Autodesk Fusion 360 part; units mm, degrees
(part 5 of 10)
sketch "Thin nut envelope sketch (6)" plane through (0, 0, 16.5) normal (0, 0, 1) x (1, 0, 0) in component "REFERENCE thin METAL channel nut front 12"
  line L0 (115.6, 222) -> (124.4, 222)
  line L1 (124.4, 222) -> (124.4, 234)
  line L2 (124.4, 234) -> (115.6, 234)
  line L3 (115.6, 234) -> (115.6, 222)
  dimension "d1899" = 115.6
  dimension "d1900" = 222
  dimension "d1901" = 8.8
  dimension "d1902" = 12
  constraint horizontal L0
  constraint vertical L1
  constraint horizontal L2
  constraint vertical L3
  measures "d1899" horizontal distance of origin L0.start
  measures "d1900" vertical distance of origin L0.start
  measures "d1901" horizontal distance of L0.start L0.end
  measures "d1902" vertical distance of L0.end L1.end
extrude "Thin nut envelope'''''" add sketch "Thin nut envelope sketch (6)" along normal blind 2.7 separate body makes body 41 in component "REFERENCE thin METAL channel nut front 12"
ref_plane "WorkPlane2" through (0, 0, 16.5) normal (0, 0, 1) x (1, 0, 0) in component "REFERENCE thin METAL channel nut front 12"
sketch "Thread envelope sketch (6)" plane through (0, 0, 16.5) normal (0, 0, 1) x (1, 0, 0) in component "REFERENCE thin METAL channel nut front 12"
  circle A0 centre (120, 228) radius 2.6
  dimension "d1907" = 120
  dimension "d1908" = 228
  dimension "d1909" = 5.2
  measures "d1907" horizontal distance of origin A0.centre
  measures "d1908" vertical distance of origin A0.centre
  measures "d1909" diameter of A0
extrude "Thread envelope'''''" cut sketch "Thread envelope sketch (6)" along normal blind 2.7 bodies 41 in component "REFERENCE thin METAL channel nut front 12"
ref_plane "WorkPlane1" through (0, 0, -5) normal (0, 0, 1) x (1, 0, 0) in component "METAL cap 20"
sketch "Visible cap sketch (7)" plane through (0, 0, -5) normal (0, 0, 1) x (1, 0, 0) in component "METAL cap 20"
  circle A0 centre (228, 12) radius 9
  dimension "d1914" = 228
  dimension "d1915" = 12
  dimension "d1916" = 18
  measures "d1914" horizontal distance of origin A0.centre
  measures "d1915" vertical distance of origin A0.centre
  measures "d1916" diameter of A0
extrude "Visible cap''''''" add sketch "Visible cap sketch (7)" along normal blind 5 separate body makes body 42 in component "METAL cap 20"
ref_plane "WorkPlane2" through (0, 0, -5) normal (0, 0, 1) x (1, 0, 0) in component "METAL cap 20"
sketch "M5 clearance sketch (7)" plane through (0, 0, -5) normal (0, 0, 1) x (1, 0, 0) in component "METAL cap 20"
  circle A0 centre (228, 12) radius 2.75
  dimension "d1921" = 228
  dimension "d1922" = 12
  dimension "d1923" = 5.5
  measures "d1921" horizontal distance of origin A0.centre
  measures "d1922" vertical distance of origin A0.centre
  measures "d1923" diameter of A0
extrude "M5 clearance''''''" cut sketch "M5 clearance sketch (7)" along normal blind 5 bodies 42 in component "METAL cap 20"
ref_plane "WorkPlane1" through (0, 0, 5) normal (0, 0, 1) x (1, 0, 0) in component "PRINT registration seat 20"
sketch "Rear bearing seat sketch (7)" plane through (0, 0, 5) normal (0, 0, 1) x (1, 0, 0) in component "PRINT registration seat 20"
  circle A0 centre (228, 12) radius 9
  dimension "d1928" = 228
  dimension "d1929" = 12
  dimension "d1930" = 18
  measures "d1928" horizontal distance of origin A0.centre
  measures "d1929" vertical distance of origin A0.centre
  measures "d1930" diameter of A0
extrude "Rear bearing seat''''''" add sketch "Rear bearing seat sketch (7)" along normal blind 2 separate body makes body 43 in component "PRINT registration seat 20"
ref_plane "WorkPlane2" through (0, 0, 5) normal (0, 0, 1) x (1, 0, 0) in component "PRINT registration seat 20"
sketch "Shoulder clearance sketch (7)" plane through (0, 0, 5) normal (0, 0, 1) x (1, 0, 0) in component "PRINT registration seat 20"
  circle A0 centre (228, 12) radius 4.2
  dimension "d1935" = 228
  dimension "d1936" = 12
  dimension "d1937" = 8.4
  measures "d1935" horizontal distance of origin A0.centre
  measures "d1936" vertical distance of origin A0.centre
  measures "d1937" diameter of A0
extrude "Shoulder clearance''''''" cut sketch "Shoulder clearance sketch (7)" along normal blind 2 bodies 43 in component "PRINT registration seat 20"
ref_plane "WorkPlane3" through (0, 0, 5) normal (0, 0, 1) x (1, 0, 0) in component "PRINT registration seat 20"
sketch "Forward registration peg sketch (9)" plane through (0, 0, 5) normal (0, 0, 1) x (1, 0, 0) in component "PRINT registration seat 20"
  circle A0 centre (223, 7) radius 1
  dimension "d1942" = 223
  dimension "d1943" = 7
  dimension "d1944" = 2
  measures "d1942" horizontal distance of origin A0.centre
  measures "d1943" vertical distance of origin A0.centre
  measures "d1944" diameter of A0
extrude "Forward registration peg''''''" add sketch "Forward registration peg sketch (9)" against normal blind 0.8 bodies 43 in component "PRINT registration seat 20"
ref_plane "WorkPlane4" through (0, 0, 5) normal (0, 0, 1) x (1, 0, 0) in component "PRINT registration seat 20"
sketch "Forward registration peg sketch (1) (7)" plane through (0, 0, 5) normal (0, 0, 1) x (1, 0, 0) in component "PRINT registration seat 20"
  circle A0 centre (223, 17) radius 1
  dimension "d1949" = 223
  dimension "d1950" = 17
  dimension "d1951" = 2
  measures "d1949" horizontal distance of origin A0.centre
  measures "d1950" vertical distance of origin A0.centre
  measures "d1951" diameter of A0
extrude "Forward registration peg (1)''''''" add sketch "Forward registration peg sketch (1) (7)" against normal blind 0.8 bodies 43 in component "PRINT registration seat 20"
ref_plane "WorkPlane5" through (0, 0, 5) normal (0, 0, 1) x (1, 0, 0) in component "PRINT registration seat 20"
sketch "Forward registration peg sketch (2) (7)" plane through (0, 0, 5) normal (0, 0, 1) x (1, 0, 0) in component "PRINT registration seat 20"
  circle A0 centre (233, 7) radius 1
  dimension "d1956" = 233
  dimension "d1957" = 7
  dimension "d1958" = 2
  measures "d1956" horizontal distance of origin A0.centre
  measures "d1957" vertical distance of origin A0.centre
  measures "d1958" diameter of A0
extrude "Forward registration peg (2)''''''" add sketch "Forward registration peg sketch (2) (7)" against normal blind 0.8 bodies 43 in component "PRINT registration seat 20"
ref_plane "WorkPlane6" through (0, 0, 5) normal (0, 0, 1) x (1, 0, 0) in component "PRINT registration seat 20"
sketch "Forward registration peg sketch (3) (7)" plane through (0, 0, 5) normal (0, 0, 1) x (1, 0, 0) in component "PRINT registration seat 20"
  circle A0 centre (233, 17) radius 1
  dimension "d1963" = 233
  dimension "d1964" = 17
  dimension "d1965" = 2
  measures "d1963" horizontal distance of origin A0.centre
  measures "d1964" vertical distance of origin A0.centre
  measures "d1965" diameter of A0
extrude "Forward registration peg (3)''''''" add sketch "Forward registration peg sketch (3) (7)" against normal blind 0.8 bodies 43 in component "PRINT registration seat 20"
sketch "8 mm shoulder sketch (7)" plane through (0, 0, 0) normal (0, 0, 1) x (1, 0, 0) in component "METAL stepped compression spacer 20"
  circle A0 centre (228, 12) radius 4
  dimension "d1968" = 228
  dimension "d1969" = 12
  dimension "d1970" = 8
  measures "d1968" horizontal distance of origin A0.centre
  measures "d1969" vertical distance of origin A0.centre
  measures "d1970" diameter of A0
extrude "8 mm shoulder''''''" add sketch "8 mm shoulder sketch (7)" along normal blind 7 separate body makes body 44 in component "METAL stepped compression spacer 20"
ref_plane "WorkPlane1" through (0, 0, 7) normal (0, 0, 1) x (1, 0, 0) in component "METAL stepped compression spacer 20"
sketch "12 mm base sketch (7)" plane through (0, 0, 7) normal (0, 0, 1) x (1, 0, 0) in component "METAL stepped compression spacer 20"
  circle A0 centre (228, 12) radius 6
  dimension "d1975" = 228
  dimension "d1976" = 12
  dimension "d1977" = 12
  measures "d1975" horizontal distance of origin A0.centre
  measures "d1976" vertical distance of origin A0.centre
  measures "d1977" diameter of A0
extrude "12 mm base''''''" add sketch "12 mm base sketch (7)" along normal blind 8 bodies 44 in component "METAL stepped compression spacer 20"
sketch "Through bore sketch (7)" plane through (0, 0, 0) normal (0, 0, 1) x (1, 0, 0) in component "METAL stepped compression spacer 20"
  circle A0 centre (228, 12) radius 2.75
  dimension "d1980" = 228
  dimension "d1981" = 12
  dimension "d1982" = 5.5
  measures "d1980" horizontal distance of origin A0.centre
  measures "d1981" vertical distance of origin A0.centre
  measures "d1982" diameter of A0
extrude "Through bore''''''" cut sketch "Through bore sketch (7)" along normal blind 15 bodies 44 in component "METAL stepped compression spacer 20"
ref_plane "WorkPlane1" through (0, 0, -8) normal (0, 0, 1) x (1, 0, 0) in component "REFERENCE front M5x25 20"
sketch "Button head envelope sketch (7)" plane through (0, 0, -8) normal (0, 0, 1) x (1, 0, 0) in component "REFERENCE front M5x25 20"
  circle A0 centre (228, 12) radius 4.75
  dimension "d1987" = 228
  dimension "d1988" = 12
  dimension "d1989" = 9.5
  measures "d1987" horizontal distance of origin A0.centre
  measures "d1988" vertical distance of origin A0.centre
  measures "d1989" diameter of A0
extrude "Button head envelope''''''" add sketch "Button head envelope sketch (7)" along normal blind 3 separate body makes body 45 in component "REFERENCE front M5x25 20"
ref_plane "WorkPlane2" through (0, 0, -5) normal (0, 0, 1) x (1, 0, 0) in component "REFERENCE front M5x25 20"
sketch "Shank envelope sketch (7)" plane through (0, 0, -5) normal (0, 0, 1) x (1, 0, 0) in component "REFERENCE front M5x25 20"
  circle A0 centre (228, 12) radius 2.5
  dimension "d1994" = 228
  dimension "d1995" = 12
  dimension "d1996" = 5
  measures "d1994" horizontal distance of origin A0.centre
  measures "d1995" vertical distance of origin A0.centre
  measures "d1996" diameter of A0
extrude "Shank envelope''''''" add sketch "Shank envelope sketch (7)" along normal blind 25 bodies 45 in component "REFERENCE front M5x25 20"
ref_plane "WorkPlane1" through (0, 0, 16.5) normal (0, 0, 1) x (1, 0, 0) in component "REFERENCE thin METAL channel nut front 20"
sketch "Thin nut envelope sketch (7)" plane through (0, 0, 16.5) normal (0, 0, 1) x (1, 0, 0) in component "REFERENCE thin METAL channel nut front 20"
  line L0 (223.6, 6) -> (232.4, 6)
  line L1 (232.4, 6) -> (232.4, 18)
  line L2 (232.4, 18) -> (223.6, 18)
  line L3 (223.6, 18) -> (223.6, 6)
  dimension "d2001" = 223.6
  dimension "d2002" = 6
  dimension "d2003" = 8.8
  dimension "d2004" = 12
  constraint horizontal L0
  constraint vertical L1
  constraint horizontal L2
  constraint vertical L3
  measures "d2001" horizontal distance of origin L0.start
  measures "d2002" vertical distance of origin L0.start
  measures "d2003" horizontal distance of L0.start L0.end
  measures "d2004" vertical distance of L0.end L1.end
extrude "Thin nut envelope''''''" add sketch "Thin nut envelope sketch (7)" along normal blind 2.7 separate body makes body 46 in component "REFERENCE thin METAL channel nut front 20"
ref_plane "WorkPlane2" through (0, 0, 16.5) normal (0, 0, 1) x (1, 0, 0) in component "REFERENCE thin METAL channel nut front 20"
sketch "Thread envelope sketch (7)" plane through (0, 0, 16.5) normal (0, 0, 1) x (1, 0, 0) in component "REFERENCE thin METAL channel nut front 20"
  circle A0 centre (228, 12) radius 2.6
  dimension "d2009" = 228
  dimension "d2010" = 12
  dimension "d2011" = 5.2
  measures "d2009" horizontal distance of origin A0.centre
  measures "d2010" vertical distance of origin A0.centre
  measures "d2011" diameter of A0
extrude "Thread envelope''''''" cut sketch "Thread envelope sketch (7)" along normal blind 2.7 bodies 46 in component "REFERENCE thin METAL channel nut front 20"
ref_plane "WorkPlane1" through (0, 0, -5) normal (0, 0, 1) x (1, 0, 0) in component "METAL cap 21"
sketch "Visible cap sketch (8)" plane through (0, 0, -5) normal (0, 0, 1) x (1, 0, 0) in component "METAL cap 21"
  circle A0 centre (228, 120) radius 9
  dimension "d2016" = 228
  dimension "d2017" = 120
  dimension "d2018" = 18
  measures "d2016" horizontal distance of origin A0.centre
  measures "d2017" vertical distance of origin A0.centre
  measures "d2018" diameter of A0
extrude "Visible cap'''''''" add sketch "Visible cap sketch (8)" along normal blind 5 separate body makes body 47 in component "METAL cap 21"
ref_plane "WorkPlane2" through (0, 0, -5) normal (0, 0, 1) x (1, 0, 0) in component "METAL cap 21"
sketch "M5 clearance sketch (8)" plane through (0, 0, -5) normal (0, 0, 1) x (1, 0, 0) in component "METAL cap 21"
  circle A0 centre (228, 120) radius 2.75
  dimension "d2023" = 228
  dimension "d2024" = 120
  dimension "d2025" = 5.5
  measures "d2023" horizontal distance of origin A0.centre
  measures "d2024" vertical distance of origin A0.centre
  measures "d2025" diameter of A0
extrude "M5 clearance'''''''" cut sketch "M5 clearance sketch (8)" along normal blind 5 bodies 47 in component "METAL cap 21"
ref_plane "WorkPlane1" through (0, 0, 5) normal (0, 0, 1) x (1, 0, 0) in component "PRINT registration seat 21"
sketch "Rear bearing seat sketch (8)" plane through (0, 0, 5) normal (0, 0, 1) x (1, 0, 0) in component "PRINT registration seat 21"
  circle A0 centre (228, 120) radius 9
  dimension "d2030" = 228
  dimension "d2031" = 120
  dimension "d2032" = 18
  measures "d2030" horizontal distance of origin A0.centre
  measures "d2031" vertical distance of origin A0.centre
  measures "d2032" diameter of A0
extrude "Rear bearing seat'''''''" add sketch "Rear bearing seat sketch (8)" along normal blind 2 separate body makes body 48 in component "PRINT registration seat 21"
ref_plane "WorkPlane2" through (0, 0, 5) normal (0, 0, 1) x (1, 0, 0) in component "PRINT registration seat 21"
sketch "Shoulder clearance sketch (8)" plane through (0, 0, 5) normal (0, 0, 1) x (1, 0, 0) in component "PRINT registration seat 21"
  circle A0 centre (228, 120) radius 4.2
  dimension "d2037" = 228
  dimension "d2038" = 120
  dimension "d2039" = 8.4
  measures "d2037" horizontal distance of origin A0.centre
  measures "d2038" vertical distance of origin A0.centre
  measures "d2039" diameter of A0
extrude "Shoulder clearance'''''''" cut sketch "Shoulder clearance sketch (8)" along normal blind 2 bodies 48 in component "PRINT registration seat 21"
ref_plane "WorkPlane3" through (0, 0, 5) normal (0, 0, 1) x (1, 0, 0) in component "PRINT registration seat 21"
sketch "Forward registration peg sketch (10)" plane through (0, 0, 5) normal (0, 0, 1) x (1, 0, 0) in component "PRINT registration seat 21"
  circle A0 centre (223, 115) radius 1
  dimension "d2044" = 223
  dimension "d2045" = 115
  dimension "d2046" = 2
  measures "d2044" horizontal distance of origin A0.centre
  measures "d2045" vertical distance of origin A0.centre
  measures "d2046" diameter of A0
extrude "Forward registration peg'''''''" add sketch "Forward registration peg sketch (10)" against normal blind 0.8 bodies 48 in component "PRINT registration seat 21"
ref_plane "WorkPlane4" through (0, 0, 5) normal (0, 0, 1) x (1, 0, 0) in component "PRINT registration seat 21"
sketch "Forward registration peg sketch (1) (8)" plane through (0, 0, 5) normal (0, 0, 1) x (1, 0, 0) in component "PRINT registration seat 21"
  circle A0 centre (223, 125) radius 1
  dimension "d2051" = 223
  dimension "d2052" = 125
  dimension "d2053" = 2
  measures "d2051" horizontal distance of origin A0.centre
  measures "d2052" vertical distance of origin A0.centre
  measures "d2053" diameter of A0
extrude "Forward registration peg (1)'''''''" add sketch "Forward registration peg sketch (1) (8)" against normal blind 0.8 bodies 48 in component "PRINT registration seat 21"
ref_plane "WorkPlane5" through (0, 0, 5) normal (0, 0, 1) x (1, 0, 0) in component "PRINT registration seat 21"
sketch "Forward registration peg sketch (2) (8)" plane through (0, 0, 5) normal (0, 0, 1) x (1, 0, 0) in component "PRINT registration seat 21"
  circle A0 centre (233, 115) radius 1
  dimension "d2058" = 233
  dimension "d2059" = 115
  dimension "d2060" = 2
  measures "d2058" horizontal distance of origin A0.centre
  measures "d2059" vertical distance of origin A0.centre
  measures "d2060" diameter of A0
extrude "Forward registration peg (2)'''''''" add sketch "Forward registration peg sketch (2) (8)" against normal blind 0.8 bodies 48 in component "PRINT registration seat 21"
ref_plane "WorkPlane6" through (0, 0, 5) normal (0, 0, 1) x (1, 0, 0) in component "PRINT registration seat 21"
sketch "Forward registration peg sketch (3) (8)" plane through (0, 0, 5) normal (0, 0, 1) x (1, 0, 0) in component "PRINT registration seat 21"
  circle A0 centre (233, 125) radius 1
  dimension "d2065" = 233
  dimension "d2066" = 125
  dimension "d2067" = 2
  measures "d2065" horizontal distance of origin A0.centre
  measures "d2066" vertical distance of origin A0.centre
  measures "d2067" diameter of A0
extrude "Forward registration peg (3)'''''''" add sketch "Forward registration peg sketch (3) (8)" against normal blind 0.8 bodies 48 in component "PRINT registration seat 21"
sketch "8 mm shoulder sketch (8)" plane through (0, 0, 0) normal (0, 0, 1) x (1, 0, 0) in component "METAL stepped compression spacer 21"
  circle A0 centre (228, 120) radius 4
  dimension "d2070" = 228
  dimension "d2071" = 120
  dimension "d2072" = 8
  measures "d2070" horizontal distance of origin A0.centre
  measures "d2071" vertical distance of origin A0.centre
  measures "d2072" diameter of A0
extrude "8 mm shoulder'''''''" add sketch "8 mm shoulder sketch (8)" along normal blind 7 separate body makes body 49 in component "METAL stepped compression spacer 21"
ref_plane "WorkPlane1" through (0, 0, 7) normal (0, 0, 1) x (1, 0, 0) in component "METAL stepped compression spacer 21"
sketch "12 mm base sketch (8)" plane through (0, 0, 7) normal (0, 0, 1) x (1, 0, 0) in component "METAL stepped compression spacer 21"
  circle A0 centre (228, 120) radius 6
  dimension "d2077" = 228
  dimension "d2078" = 120
  dimension "d2079" = 12
  measures "d2077" horizontal distance of origin A0.centre
  measures "d2078" vertical distance of origin A0.centre
  measures "d2079" diameter of A0
extrude "12 mm base'''''''" add sketch "12 mm base sketch (8)" along normal blind 8 bodies 49 in component "METAL stepped compression spacer 21"
sketch "Through bore sketch (8)" plane through (0, 0, 0) normal (0, 0, 1) x (1, 0, 0) in component "METAL stepped compression spacer 21"
  circle A0 centre (228, 120) radius 2.75
  dimension "d2082" = 228
  dimension "d2083" = 120
  dimension "d2084" = 5.5
  measures "d2082" horizontal distance of origin A0.centre
  measures "d2083" vertical distance of origin A0.centre
  measures "d2084" diameter of A0
extrude "Through bore'''''''" cut sketch "Through bore sketch (8)" along normal blind 15 bodies 49 in component "METAL stepped compression spacer 21"
ref_plane "WorkPlane1" through (0, 0, -8) normal (0, 0, 1) x (1, 0, 0) in component "REFERENCE front M5x25 21"
sketch "Button head envelope sketch (8)" plane through (0, 0, -8) normal (0, 0, 1) x (1, 0, 0) in component "REFERENCE front M5x25 21"
  circle A0 centre (228, 120) radius 4.75
  dimension "d2089" = 228
  dimension "d2090" = 120
  dimension "d2091" = 9.5
  measures "d2089" horizontal distance of origin A0.centre
  measures "d2090" vertical distance of origin A0.centre
  measures "d2091" diameter of A0
extrude "Button head envelope'''''''" add sketch "Button head envelope sketch (8)" along normal blind 3 separate body makes body 50 in component "REFERENCE front M5x25 21"
ref_plane "WorkPlane2" through (0, 0, -5) normal (0, 0, 1) x (1, 0, 0) in component "REFERENCE front M5x25 21"
sketch "Shank envelope sketch (8)" plane through (0, 0, -5) normal (0, 0, 1) x (1, 0, 0) in component "REFERENCE front M5x25 21"
  circle A0 centre (228, 120) radius 2.5
  dimension "d2096" = 228
  dimension "d2097" = 120
  dimension "d2098" = 5
  measures "d2096" horizontal distance of origin A0.centre
  measures "d2097" vertical distance of origin A0.centre
  measures "d2098" diameter of A0
extrude "Shank envelope'''''''" add sketch "Shank envelope sketch (8)" along normal blind 25 bodies 50 in component "REFERENCE front M5x25 21"
ref_plane "WorkPlane1" through (0, 0, 16.5) normal (0, 0, 1) x (1, 0, 0) in component "REFERENCE thin METAL channel nut front 21"
sketch "Thin nut envelope sketch (8)" plane through (0, 0, 16.5) normal (0, 0, 1) x (1, 0, 0) in component "REFERENCE thin METAL channel nut front 21"
  line L0 (223.6, 114) -> (232.4, 114)
  line L1 (232.4, 114) -> (232.4, 126)
  line L2 (232.4, 126) -> (223.6, 126)
  line L3 (223.6, 126) -> (223.6, 114)
  dimension "d2103" = 223.6
  dimension "d2104" = 114
  dimension "d2105" = 8.8
  dimension "d2106" = 12
  constraint horizontal L0
  constraint vertical L1
  constraint horizontal L2
  constraint vertical L3
  measures "d2103" horizontal distance of origin L0.start
  measures "d2104" vertical distance of origin L0.start
  measures "d2105" horizontal distance of L0.start L0.end
  measures "d2106" vertical distance of L0.end L1.end
extrude "Thin nut envelope'''''''" add sketch "Thin nut envelope sketch (8)" along normal blind 2.7 separate body makes body 51 in component "REFERENCE thin METAL channel nut front 21"
ref_plane "WorkPlane2" through (0, 0, 16.5) normal (0, 0, 1) x (1, 0, 0) in component "REFERENCE thin METAL channel nut front 21"
sketch "Thread envelope sketch (8)" plane through (0, 0, 16.5) normal (0, 0, 1) x (1, 0, 0) in component "REFERENCE thin METAL channel nut front 21"
  circle A0 centre (228, 120) radius 2.6
  dimension "d2111" = 228
  dimension "d2112" = 120
  dimension "d2113" = 5.2
  measures "d2111" horizontal distance of origin A0.centre
  measures "d2112" vertical distance of origin A0.centre
  measures "d2113" diameter of A0
extrude "Thread envelope'''''''" cut sketch "Thread envelope sketch (8)" along normal blind 2.7 bodies 51 in component "REFERENCE thin METAL channel nut front 21"
ref_plane "WorkPlane1" through (0, 0, -5) normal (0, 0, 1) x (1, 0, 0) in component "METAL cap 22"
sketch "Visible cap sketch (9)" plane through (0, 0, -5) normal (0, 0, 1) x (1, 0, 0) in component "METAL cap 22"
  circle A0 centre (228, 228) radius 9
  dimension "d2118" = 228
  dimension "d2119" = 228
  dimension "d2120" = 18
  measures "d2118" horizontal distance of origin A0.centre
  measures "d2119" vertical distance of origin A0.centre
  measures "d2120" diameter of A0
extrude "Visible cap''''''''" add sketch "Visible cap sketch (9)" along normal blind 5 separate body makes body 52 in component "METAL cap 22"
ref_plane "WorkPlane2" through (0, 0, -5) normal (0, 0, 1) x (1, 0, 0) in component "METAL cap 22"
sketch "M5 clearance sketch (9)" plane through (0, 0, -5) normal (0, 0, 1) x (1, 0, 0) in component "METAL cap 22"
  circle A0 centre (228, 228) radius 2.75
  dimension "d2125" = 228
  dimension "d2126" = 228
  dimension "d2127" = 5.5
  measures "d2125" horizontal distance of origin A0.centre
  measures "d2126" vertical distance of origin A0.centre
  measures "d2127" diameter of A0
extrude "M5 clearance''''''''" cut sketch "M5 clearance sketch (9)" along normal blind 5 bodies 52 in component "METAL cap 22"
ref_plane "WorkPlane1" through (0, 0, 5) normal (0, 0, 1) x (1, 0, 0) in component "PRINT registration seat 22"
sketch "Rear bearing seat sketch (9)" plane through (0, 0, 5) normal (0, 0, 1) x (1, 0, 0) in component "PRINT registration seat 22"
  circle A0 centre (228, 228) radius 9
  dimension "d2132" = 228
  dimension "d2133" = 228
  dimension "d2134" = 18
  measures "d2132" horizontal distance of origin A0.centre
  measures "d2133" vertical distance of origin A0.centre
  measures "d2134" diameter of A0
extrude "Rear bearing seat''''''''" add sketch "Rear bearing seat sketch (9)" along normal blind 2 separate body makes body 53 in component "PRINT registration seat 22"
ref_plane "WorkPlane2" through (0, 0, 5) normal (0, 0, 1) x (1, 0, 0) in component "PRINT registration seat 22"
sketch "Shoulder clearance sketch (9)" plane through (0, 0, 5) normal (0, 0, 1) x (1, 0, 0) in component "PRINT registration seat 22"
  circle A0 centre (228, 228) radius 4.2
  dimension "d2139" = 228
  dimension "d2140" = 228
  dimension "d2141" = 8.4
  measures "d2139" horizontal distance of origin A0.centre
  measures "d2140" vertical distance of origin A0.centre
  measures "d2141" diameter of A0
extrude "Shoulder clearance''''''''" cut sketch "Shoulder clearance sketch (9)" along normal blind 2 bodies 53 in component "PRINT registration seat 22"
ref_plane "WorkPlane3" through (0, 0, 5) normal (0, 0, 1) x (1, 0, 0) in component "PRINT registration seat 22"
sketch "Forward registration peg sketch (11)" plane through (0, 0, 5) normal (0, 0, 1) x (1, 0, 0) in component "PRINT registration seat 22"
  circle A0 centre (223, 223) radius 1
  dimension "d2146" = 223
  dimension "d2147" = 223
  dimension "d2148" = 2
  measures "d2146" horizontal distance of origin A0.centre
  measures "d2147" vertical distance of origin A0.centre
  measures "d2148" diameter of A0
extrude "Forward registration peg''''''''" add sketch "Forward registration peg sketch (11)" against normal blind 0.8 bodies 53 in component "PRINT registration seat 22"
ref_plane "WorkPlane4" through (0, 0, 5) normal (0, 0, 1) x (1, 0, 0) in component "PRINT registration seat 22"
sketch "Forward registration peg sketch (1) (9)" plane through (0, 0, 5) normal (0, 0, 1) x (1, 0, 0) in component "PRINT registration seat 22"
  circle A0 centre (223, 233) radius 1
  dimension "d2153" = 223
  dimension "d2154" = 233
  dimension "d2155" = 2
  measures "d2153" horizontal distance of origin A0.centre
  measures "d2154" vertical distance of origin A0.centre
  measures "d2155" diameter of A0
extrude "Forward registration peg (1)''''''''" add sketch "Forward registration peg sketch (1) (9)" against normal blind 0.8 bodies 53 in component "PRINT registration seat 22"
ref_plane "WorkPlane5" through (0, 0, 5) normal (0, 0, 1) x (1, 0, 0) in component "PRINT registration seat 22"
sketch "Forward registration peg sketch (2) (9)" plane through (0, 0, 5) normal (0, 0, 1) x (1, 0, 0) in component "PRINT registration seat 22"
  circle A0 centre (233, 223) radius 1
  dimension "d2160" = 233
  dimension "d2161" = 223
  dimension "d2162" = 2
  measures "d2160" horizontal distance of origin A0.centre
  measures "d2161" vertical distance of origin A0.centre
  measures "d2162" diameter of A0
extrude "Forward registration peg (2)''''''''" add sketch "Forward registration peg sketch (2) (9)" against normal blind 0.8 bodies 53 in component "PRINT registration seat 22"
ref_plane "WorkPlane6" through (0, 0, 5) normal (0, 0, 1) x (1, 0, 0) in component "PRINT registration seat 22"
sketch "Forward registration peg sketch (3) (9)" plane through (0, 0, 5) normal (0, 0, 1) x (1, 0, 0) in component "PRINT registration seat 22"
  circle A0 centre (233, 233) radius 1
  dimension "d2167" = 233
  dimension "d2168" = 233
  dimension "d2169" = 2
  measures "d2167" horizontal distance of origin A0.centre
  measures "d2168" vertical distance of origin A0.centre
  measures "d2169" diameter of A0
extrude "Forward registration peg (3)''''''''" add sketch "Forward registration peg sketch (3) (9)" against normal blind 0.8 bodies 53 in component "PRINT registration seat 22"
sketch "8 mm shoulder sketch (9)" plane through (0, 0, 0) normal (0, 0, 1) x (1, 0, 0) in component "METAL stepped compression spacer 22"
  circle A0 centre (228, 228) radius 4
  dimension "d2172" = 228
  dimension "d2173" = 228
  dimension "d2174" = 8
  measures "d2172" horizontal distance of origin A0.centre
  measures "d2173" vertical distance of origin A0.centre
  measures "d2174" diameter of A0
extrude "8 mm shoulder''''''''" add sketch "8 mm shoulder sketch (9)" along normal blind 7 separate body makes body 54 in component "METAL stepped compression spacer 22"
ref_plane "WorkPlane1" through (0, 0, 7) normal (0, 0, 1) x (1, 0, 0) in component "METAL stepped compression spacer 22"
sketch "12 mm base sketch (9)" plane through (0, 0, 7) normal (0, 0, 1) x (1, 0, 0) in component "METAL stepped compression spacer 22"
  circle A0 centre (228, 228) radius 6
  dimension "d2179" = 228
  dimension "d2180" = 228
  dimension "d2181" = 12
  measures "d2179" horizontal distance of origin A0.centre
  measures "d2180" vertical distance of origin A0.centre
  measures "d2181" diameter of A0
extrude "12 mm base''''''''" add sketch "12 mm base sketch (9)" along normal blind 8 bodies 54 in component "METAL stepped compression spacer 22"
sketch "Through bore sketch (9)" plane through (0, 0, 0) normal (0, 0, 1) x (1, 0, 0) in component "METAL stepped compression spacer 22"
  circle A0 centre (228, 228) radius 2.75
  dimension "d2184" = 228
  dimension "d2185" = 228
  dimension "d2186" = 5.5
  measures "d2184" horizontal distance of origin A0.centre
  measures "d2185" vertical distance of origin A0.centre
  measures "d2186" diameter of A0
extrude "Through bore''''''''" cut sketch "Through bore sketch (9)" along normal blind 15 bodies 54 in component "METAL stepped compression spacer 22"
ref_plane "WorkPlane1" through (0, 0, -8) normal (0, 0, 1) x (1, 0, 0) in component "REFERENCE front M5x25 22"
sketch "Button head envelope sketch (9)" plane through (0, 0, -8) normal (0, 0, 1) x (1, 0, 0) in component "REFERENCE front M5x25 22"
  circle A0 centre (228, 228) radius 4.75
  dimension "d2191" = 228
  dimension "d2192" = 228
  dimension "d2193" = 9.5
  measures "d2191" horizontal distance of origin A0.centre
  measures "d2192" vertical distance of origin A0.centre
  measures "d2193" diameter of A0
extrude "Button head envelope''''''''" add sketch "Button head envelope sketch (9)" along normal blind 3 separate body makes body 55 in component "REFERENCE front M5x25 22"
ref_plane "WorkPlane2" through (0, 0, -5) normal (0, 0, 1) x (1, 0, 0) in component "REFERENCE front M5x25 22"
sketch "Shank envelope sketch (9)" plane through (0, 0, -5) normal (0, 0, 1) x (1, 0, 0) in component "REFERENCE front M5x25 22"
  circle A0 centre (228, 228) radius 2.5
  dimension "d2198" = 228
  dimension "d2199" = 228
  dimension "d2200" = 5
  measures "d2198" horizontal distance of origin A0.centre
  measures "d2199" vertical distance of origin A0.centre
  measures "d2200" diameter of A0
extrude "Shank envelope''''''''" add sketch "Shank envelope sketch (9)" along normal blind 25 bodies 55 in component "REFERENCE front M5x25 22"
ref_plane "WorkPlane1" through (0, 0, 16.5) normal (0, 0, 1) x (1, 0, 0) in component "REFERENCE thin METAL channel nut front 22"
sketch "Thin nut envelope sketch (9)" plane through (0, 0, 16.5) normal (0, 0, 1) x (1, 0, 0) in component "REFERENCE thin METAL channel nut front 22"
  line L0 (223.6, 222) -> (232.4, 222)
  line L1 (232.4, 222) -> (232.4, 234)
  line L2 (232.4, 234) -> (223.6, 234)
  line L3 (223.6, 234) -> (223.6, 222)
  dimension "d2205" = 223.6
  dimension "d2206" = 222
  dimension "d2207" = 8.8
  dimension "d2208" = 12
  constraint horizontal L0
  constraint vertical L1
  constraint horizontal L2
  constraint vertical L3
  measures "d2205" horizontal distance of origin L0.start
  measures "d2206" vertical distance of origin L0.start
  measures "d2207" horizontal distance of L0.start L0.end
  measures "d2208" vertical distance of L0.end L1.end
extrude "Thin nut envelope''''''''" add sketch "Thin nut envelope sketch (9)" along normal blind 2.7 separate body makes body 56 in component "REFERENCE thin METAL channel nut front 22"
ref_plane "WorkPlane2" through (0, 0, 16.5) normal (0, 0, 1) x (1, 0, 0) in component "REFERENCE thin METAL channel nut front 22"
sketch "Thread envelope sketch (9)" plane through (0, 0, 16.5) normal (0, 0, 1) x (1, 0, 0) in component "REFERENCE thin METAL channel nut front 22"
  circle A0 centre (228, 228) radius 2.6
  dimension "d2213" = 228
  dimension "d2214" = 228
  dimension "d2215" = 5.2
  measures "d2213" horizontal distance of origin A0.centre
  measures "d2214" vertical distance of origin A0.centre
  measures "d2215" diameter of A0
extrude "Thread envelope''''''''" cut sketch "Thread envelope sketch (9)" along normal blind 2.7 bodies 56 in component "REFERENCE thin METAL channel nut front 22"
ref_plane "WorkPlane1" through (0, 0, 17) normal (0, 0, 1) x (1, 0, 0) in component "METAL in-bay corner 00L"
sketch "Vertical bracket leg sketch" plane through (0, 0, 17) normal (0, 0, 1) x (1, 0, 0) in component "METAL in-bay corner 00L"
  line L0 (22, 22) -> (25, 22)
  line L1 (25, 22) -> (25, 40)
  line L2 (25, 40) -> (22, 40)
  line L3 (22, 40) -> (22, 22)
  dimension "d2220" = 22
  dimension "d2221" = 22
  dimension "d2222" = 3
  dimension "d2223" = 18
  constraint horizontal L0
  constraint vertical L1
  constraint horizontal L2
  constraint vertical L3
  measures "d2220" horizontal distance of origin L0.start
  measures "d2221" vertical distance of origin L0.start
  measures "d2222" horizontal distance of L0.start L0.end
  measures "d2223" vertical distance of L0.end L1.end
extrude "Vertical bracket leg" add sketch "Vertical bracket leg sketch" along normal blind 16 separate body makes body 57 in component "METAL in-bay corner 00L"
ref_plane "WorkPlane2" through (0, 0, 17) normal (0, 0, 1) x (1, 0, 0) in component "METAL in-bay corner 00L"
sketch "Horizontal bracket leg sketch" plane through (0, 0, 17) normal (0, 0, 1) x (1, 0, 0) in component "METAL in-bay corner 00L"
  line L0 (22, 22) -> (40, 22)
  line L1 (40, 22) -> (40, 25)
  line L2 (40, 25) -> (22, 25)
  line L3 (22, 25) -> (22, 22)
  dimension "d2228" = 22
  dimension "d2229" = 22
  dimension "d2230" = 18
  dimension "d2231" = 3
  constraint horizontal L0
  constraint vertical L1
  constraint horizontal L2
  constraint vertical L3
  measures "d2228" horizontal distance of origin L0.start
  measures "d2229" vertical distance of origin L0.start
  measures "d2230" horizontal distance of L0.start L0.end
  measures "d2231" vertical distance of L0.end L1.end
extrude "Horizontal bracket leg" add sketch "Horizontal bracket leg sketch" along normal blind 16 bodies 57 in component "METAL in-bay corner 00L"
ref_plane "WorkPlane3" through (22, 0, 0) normal (1, 0, 0) x (0, 1, 0) in component "METAL in-bay corner 00L"
sketch "Vertical rail bolt sketch" plane through (22, 0, 0) normal (1, 0, 0) x (0, 0, -1) in component "METAL in-bay corner 00L"
  circle A0 centre (-25, 34) radius 2.75
  dimension "d2236" = 25
  dimension "d2237" = 34
  dimension "d2238" = 5.5
  measures "d2236" horizontal distance of origin A0.centre
  measures "d2237" vertical distance of origin A0.centre
  measures "d2238" diameter of A0
extrude "Vertical rail bolt" cut sketch "Vertical rail bolt sketch" along normal blind 3 bodies 57 in component "METAL in-bay corner 00L"
ref_plane "WorkPlane4" through (0, 22, 0) normal (0, 1, 0) x (0, 0, 1) in component "METAL in-bay corner 00L"
sketch "Tie bolt sketch" plane through (0, 22, 0) normal (0, 1, 0) x (1, 0, 0) in component "METAL in-bay corner 00L"
  circle A0 centre (34, -25) radius 2.75
  dimension "d2243" = 34
  dimension "d2244" = 25
  dimension "d2245" = 5.5
  measures "d2243" horizontal distance of origin A0.centre
  measures "d2244" vertical distance of origin A0.centre
  measures "d2245" diameter of A0
extrude "Tie bolt" cut sketch "Tie bolt sketch" along normal blind 3 bodies 57 in component "METAL in-bay corner 00L"
ref_plane "WorkPlane1" through (25, 0, 0) normal (1, 0, 0) x (0, 1, 0) in component "REFERENCE side M5x8 00L X"
sketch "Button head envelope sketch (10)" plane through (25, 0, 0) normal (1, 0, 0) x (0, 0, -1) in component "REFERENCE side M5x8 00L X"
  circle A0 centre (-25, 34) radius 4.75
  dimension "d2250" = 25
  dimension "d2251" = 34
  dimension "d2252" = 9.5
  measures "d2250" horizontal distance of origin A0.centre
  measures "d2251" vertical distance of origin A0.centre
  measures "d2252" diameter of A0
extrude "Button head envelope'''''''''" add sketch "Button head envelope sketch (10)" along normal blind 3 separate body makes body 58 in component "REFERENCE side M5x8 00L X"
ref_plane "WorkPlane2" through (25, 0, 0) normal (1, 0, 0) x (0, 1, 0) in component "REFERENCE side M5x8 00L X"
sketch "Shank envelope sketch (10)" plane through (25, 0, 0) normal (1, 0, 0) x (0, 0, -1) in component "REFERENCE side M5x8 00L X"
  circle A0 centre (-25, 34) radius 2.5
  dimension "d2257" = 25
  dimension "d2258" = 34
  dimension "d2259" = 5
  measures "d2257" horizontal distance of origin A0.centre
  measures "d2258" vertical distance of origin A0.centre
  measures "d2259" diameter of A0
extrude "Shank envelope'''''''''" add sketch "Shank envelope sketch (10)" against normal blind 8 bodies 58 in component "REFERENCE side M5x8 00L X"
ref_plane "WorkPlane1" through (0, 0, 20.6) normal (0, 0, 1) x (1, 0, 0) in component "REFERENCE thin METAL channel nut side 00L X"
sketch "Thin nut envelope sketch (10)" plane through (0, 0, 20.6) normal (0, 0, 1) x (1, 0, 0) in component "REFERENCE thin METAL channel nut side 00L X"
  line L0 (17.8, 28) -> (20.5, 28)
  line L1 (20.5, 28) -> (20.5, 40)
  line L2 (20.5, 40) -> (17.8, 40)
  line L3 (17.8, 40) -> (17.8, 28)
  dimension "d2264" = 17.8
  dimension "d2265" = 28
  dimension "d2266" = 2.7
  dimension "d2267" = 12
  constraint horizontal L0
  constraint vertical L1
  constraint horizontal L2
  constraint vertical L3
  measures "d2264" horizontal distance of origin L0.start
  measures "d2265" vertical distance of origin L0.start
  measures "d2266" horizontal distance of L0.start L0.end
  measures "d2267" vertical distance of L0.end L1.end
extrude "Thin nut envelope'''''''''" add sketch "Thin nut envelope sketch (10)" along normal blind 8.8 separate body makes body 59 in component "REFERENCE thin METAL channel nut side 00L X"
ref_plane "WorkPlane2" through (17.8, 0, 0) normal (1, 0, 0) x (0, 1, 0) in component "REFERENCE thin METAL channel nut side 00L X"
sketch "Thread envelope sketch (10)" plane through (17.8, 0, 0) normal (1, 0, 0) x (0, 0, -1) in component "REFERENCE thin METAL channel nut side 00L X"
  circle A0 centre (-25, 34) radius 2.6
  dimension "d2272" = 25
  dimension "d2273" = 34
  dimension "d2274" = 5.2
  measures "d2272" horizontal distance of origin A0.centre
  measures "d2273" vertical distance of origin A0.centre
  measures "d2274" diameter of A0
extrude "Thread envelope'''''''''" cut sketch "Thread envelope sketch (10)" along normal blind 2.7 bodies 59 in component "REFERENCE thin METAL channel nut side 00L X"
ref_plane "WorkPlane1" through (0, 25, 0) normal (0, 1, 0) x (0, 0, 1) in component "REFERENCE side M5x8 00L Y"
sketch "Button head envelope sketch (11)" plane through (0, 25, 0) normal (0, 1, 0) x (1, 0, 0) in component "REFERENCE side M5x8 00L Y"
  circle A0 centre (34, -25) radius 4.75
  dimension "d2279" = 34
  dimension "d2280" = 25
  dimension "d2281" = 9.5
  measures "d2279" horizontal distance of origin A0.centre
  measures "d2280" vertical distance of origin A0.centre
  measures "d2281" diameter of A0
extrude "Button head envelope''''''''''" add sketch "Button head envelope sketch (11)" along normal blind 3 separate body makes body 60 in component "REFERENCE side M5x8 00L Y"
ref_plane "WorkPlane2" through (0, 25, 0) normal (0, 1, 0) x (0, 0, 1) in component "REFERENCE side M5x8 00L Y"
sketch "Shank envelope sketch (11)" plane through (0, 25, 0) normal (0, 1, 0) x (1, 0, 0) in component "REFERENCE side M5x8 00L Y"
  circle A0 centre (34, -25) radius 2.5
  dimension "d2286" = 34
  dimension "d2287" = 25
  dimension "d2288" = 5
  measures "d2286" horizontal distance of origin A0.centre
  measures "d2287" vertical distance of origin A0.centre
  measures "d2288" diameter of A0
extrude "Shank envelope''''''''''" add sketch "Shank envelope sketch (11)" against normal blind 8 bodies 60 in component "REFERENCE side M5x8 00L Y"
ref_plane "WorkPlane1" through (0, 0, 20.6) normal (0, 0, 1) x (1, 0, 0) in component "REFERENCE thin METAL channel nut side 00L Y"
sketch "Thin nut envelope sketch (11)" plane through (0, 0, 20.6) normal (0, 0, 1) x (1, 0, 0) in component "REFERENCE thin METAL channel nut side 00L Y"
  line L0 (28, 17.8) -> (40, 17.8)
  line L1 (40, 17.8) -> (40, 20.5)
  line L2 (40, 20.5) -> (28, 20.5)
  line L3 (28, 20.5) -> (28, 17.8)
  dimension "d2293" = 28
  dimension "d2294" = 17.8
  dimension "d2295" = 12
  dimension "d2296" = 2.7
  constraint horizontal L0
  constraint vertical L1
  constraint horizontal L2
  constraint vertical L3
  measures "d2293" horizontal distance of origin L0.start
  measures "d2294" vertical distance of origin L0.start
  measures "d2295" horizontal distance of L0.start L0.end
  measures "d2296" vertical distance of L0.end L1.end
extrude "Thin nut envelope''''''''''" add sketch "Thin nut envelope sketch (11)" along normal blind 8.8 separate body makes body 61 in component "REFERENCE thin METAL channel nut side 00L Y"
ref_plane "WorkPlane2" through (0, 17.8, 0) normal (0, 1, 0) x (0, 0, 1) in component "REFERENCE thin METAL channel nut side 00L Y"
sketch "Thread envelope sketch (11)" plane through (0, 17.8, 0) normal (0, 1, 0) x (1, 0, 0) in component "REFERENCE thin METAL channel nut side 00L Y"
  circle A0 centre (34, -25) radius 2.6
  dimension "d2301" = 34
  dimension "d2302" = 25
  dimension "d2303" = 5.2
  measures "d2301" horizontal distance of origin A0.centre
  measures "d2302" vertical distance of origin A0.centre
  measures "d2303" diameter of A0
extrude "Thread envelope''''''''''" cut sketch "Thread envelope sketch (11)" along normal blind 2.7 bodies 61 in component "REFERENCE thin METAL channel nut side 00L Y"
ref_plane "WorkPlane1" through (0, 0, 17) normal (0, 0, 1) x (1, 0, 0) in component "METAL in-bay corner 00R"
sketch "Vertical bracket leg sketch (2)" plane through (0, 0, 17) normal (0, 0, 1) x (1, 0, 0) in component "METAL in-bay corner 00R"
  line L0 (107, 22) -> (110, 22)
  line L1 (110, 22) -> (110, 40)
  line L2 (110, 40) -> (107, 40)
  line L3 (107, 40) -> (107, 22)
  dimension "d2308" = 107
  dimension "d2309" = 22
  dimension "d2310" = 3
  dimension "d2311" = 18
  constraint horizontal L0
  constraint vertical L1
  constraint horizontal L2
  constraint vertical L3
  measures "d2308" horizontal distance of origin L0.start
  measures "d2309" vertical distance of origin L0.start
  measures "d2310" horizontal distance of L0.start L0.end
  measures "d2311" vertical distance of L0.end L1.end
extrude "Vertical bracket leg'" add sketch "Vertical bracket leg sketch (2)" along normal blind 16 separate body makes body 62 in component "METAL in-bay corner 00R"
ref_plane "WorkPlane2" through (0, 0, 17) normal (0, 0, 1) x (1, 0, 0) in component "METAL in-bay corner 00R"
sketch "Horizontal bracket leg sketch (2)" plane through (0, 0, 17) normal (0, 0, 1) x (1, 0, 0) in component "METAL in-bay corner 00R"
  line L0 (92, 22) -> (110, 22)
  line L1 (110, 22) -> (110, 25)
  line L2 (110, 25) -> (92, 25)
  line L3 (92, 25) -> (92, 22)
  dimension "d2316" = 92
  dimension "d2317" = 22
  dimension "d2318" = 18
  dimension "d2319" = 3
  constraint horizontal L0
  constraint vertical L1
  constraint horizontal L2
  constraint vertical L3
  measures "d2316" horizontal distance of origin L0.start
  measures "d2317" vertical distance of origin L0.start
  measures "d2318" horizontal distance of L0.start L0.end
  measures "d2319" vertical distance of L0.end L1.end
extrude "Horizontal bracket leg'" add sketch "Horizontal bracket leg sketch (2)" along normal blind 16 bodies 62 in component "METAL in-bay corner 00R"
ref_plane "WorkPlane3" through (110, 0, 0) normal (1, 0, 0) x (0, 1, 0) in component "METAL in-bay corner 00R"
sketch "Vertical rail bolt sketch (2)" plane through (110, 0, 0) normal (1, 0, 0) x (0, 0, -1) in component "METAL in-bay corner 00R"
  circle A0 centre (-25, 34) radius 2.75
  dimension "d2324" = 25
  dimension "d2325" = 34
  dimension "d2326" = 5.5
  measures "d2324" horizontal distance of origin A0.centre
  measures "d2325" vertical distance of origin A0.centre
  measures "d2326" diameter of A0
extrude "Vertical rail bolt'" cut sketch "Vertical rail bolt sketch (2)" against normal blind 3 bodies 62 in component "METAL in-bay corner 00R"
ref_plane "WorkPlane4" through (0, 22, 0) normal (0, 1, 0) x (0, 0, 1) in component "METAL in-bay corner 00R"
sketch "Tie bolt sketch (2)" plane through (0, 22, 0) normal (0, 1, 0) x (1, 0, 0) in component "METAL in-bay corner 00R"
  circle A0 centre (98, -25) radius 2.75
  dimension "d2331" = 98
  dimension "d2332" = 25
  dimension "d2333" = 5.5
  measures "d2331" horizontal distance of origin A0.centre
  measures "d2332" vertical distance of origin A0.centre
  measures "d2333" diameter of A0
extrude "Tie bolt'" cut sketch "Tie bolt sketch (2)" along normal blind 3 bodies 62 in component "METAL in-bay corner 00R"
ref_plane "WorkPlane1" through (107, 0, 0) normal (1, 0, 0) x (0, 1, 0) in component "REFERENCE side M5x8 00R X"
sketch "Button head envelope sketch (12)" plane through (107, 0, 0) normal (1, 0, 0) x (0, 0, -1) in component "REFERENCE side M5x8 00R X"
  circle A0 centre (-25, 34) radius 4.75
  dimension "d2338" = 25
  dimension "d2339" = 34
  dimension "d2340" = 9.5
  measures "d2338" horizontal distance of origin A0.centre
  measures "d2339" vertical distance of origin A0.centre
  measures "d2340" diameter of A0
extrude "Button head envelope'''''''''''" add sketch "Button head envelope sketch (12)" against normal blind 3 separate body makes body 63 in component "REFERENCE side M5x8 00R X"
ref_plane "WorkPlane2" through (107, 0, 0) normal (1, 0, 0) x (0, 1, 0) in component "REFERENCE side M5x8 00R X"
sketch "Shank envelope sketch (12)" plane through (107, 0, 0) normal (1, 0, 0) x (0, 0, -1) in component "REFERENCE side M5x8 00R X"
  circle A0 centre (-25, 34) radius 2.5
  dimension "d2345" = 25
  dimension "d2346" = 34
  dimension "d2347" = 5
  measures "d2345" horizontal distance of origin A0.centre
  measures "d2346" vertical distance of origin A0.centre
  measures "d2347" diameter of A0
extrude "Shank envelope'''''''''''" add sketch "Shank envelope sketch (12)" along normal blind 8 bodies 63 in component "REFERENCE side M5x8 00R X"
ref_plane "WorkPlane1" through (0, 0, 20.6) normal (0, 0, 1) x (1, 0, 0) in component "REFERENCE thin METAL channel nut side 00R X"
sketch "Thin nut envelope sketch (12)" plane through (0, 0, 20.6) normal (0, 0, 1) x (1, 0, 0) in component "REFERENCE thin METAL channel nut side 00R X"
  line L0 (111.5, 28) -> (114.2, 28)
  line L1 (114.2, 28) -> (114.2, 40)
  line L2 (114.2, 40) -> (111.5, 40)
  line L3 (111.5, 40) -> (111.5, 28)
  dimension "d2352" = 111.5
  dimension "d2353" = 28
  dimension "d2354" = 2.7
  dimension "d2355" = 12
  constraint horizontal L0
  constraint vertical L1
  constraint horizontal L2
  constraint vertical L3
  measures "d2352" horizontal distance of origin L0.start
  measures "d2353" vertical distance of origin L0.start
  measures "d2354" horizontal distance of L0.start L0.end
  measures "d2355" vertical distance of L0.end L1.end
extrude "Thin nut envelope'''''''''''" add sketch "Thin nut envelope sketch (12)" along normal blind 8.8 separate body makes body 64 in component "REFERENCE thin METAL channel nut side 00R X"
ref_plane "WorkPlane2" through (111.5, 0, 0) normal (1, 0, 0) x (0, 1, 0) in component "REFERENCE thin METAL channel nut side 00R X"
sketch "Thread envelope sketch (12)" plane through (111.5, 0, 0) normal (1, 0, 0) x (0, 0, -1) in component "REFERENCE thin METAL channel nut side 00R X"
  circle A0 centre (-25, 34) radius 2.6
  dimension "d2360" = 25
  dimension "d2361" = 34
  dimension "d2362" = 5.2
  measures "d2360" horizontal distance of origin A0.centre
  measures "d2361" vertical distance of origin A0.centre
  measures "d2362" diameter of A0
extrude "Thread envelope'''''''''''" cut sketch "Thread envelope sketch (12)" along normal blind 2.7 bodies 64 in component "REFERENCE thin METAL channel nut side 00R X"
ref_plane "WorkPlane1" through (0, 25, 0) normal (0, 1, 0) x (0, 0, 1) in component "REFERENCE side M5x8 00R Y"
sketch "Button head envelope sketch (13)" plane through (0, 25, 0) normal (0, 1, 0) x (1, 0, 0) in component "REFERENCE side M5x8 00R Y"
  circle A0 centre (98, -25) radius 4.75
  dimension "d2367" = 98
  dimension "d2368" = 25
  dimension "d2369" = 9.5
  measures "d2367" horizontal distance of origin A0.centre
  measures "d2368" vertical distance of origin A0.centre
  measures "d2369" diameter of A0
extrude "Button head envelope''''''''''''" add sketch "Button head envelope sketch (13)" along normal blind 3 separate body makes body 65 in component "REFERENCE side M5x8 00R Y"
ref_plane "WorkPlane2" through (0, 25, 0) normal (0, 1, 0) x (0, 0, 1) in component "REFERENCE side M5x8 00R Y"
sketch "Shank envelope sketch (13)" plane through (0, 25, 0) normal (0, 1, 0) x (1, 0, 0) in component "REFERENCE side M5x8 00R Y"
  circle A0 centre (98, -25) radius 2.5
  dimension "d2374" = 98
  dimension "d2375" = 25
  dimension "d2376" = 5
  measures "d2374" horizontal distance of origin A0.centre
  measures "d2375" vertical distance of origin A0.centre
  measures "d2376" diameter of A0
extrude "Shank envelope''''''''''''" add sketch "Shank envelope sketch (13)" against normal blind 8 bodies 65 in component "REFERENCE side M5x8 00R Y"
ref_plane "WorkPlane1" through (0, 0, 20.6) normal (0, 0, 1) x (1, 0, 0) in component "REFERENCE thin METAL channel nut side 00R Y"